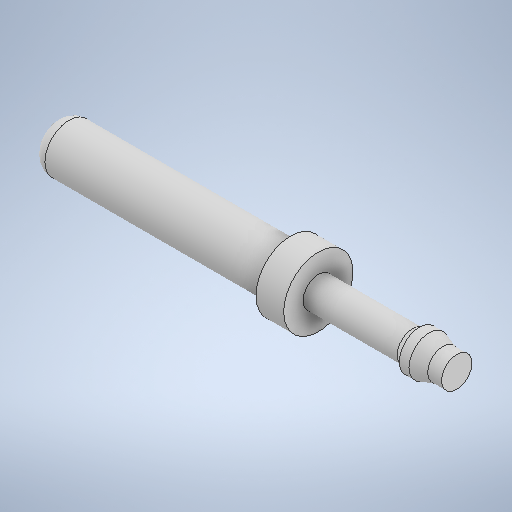
# Autodesk Inventor part: water_release_spring_v6
Saved by Autodesk Inventor 2025.2 (Build 292293000, 293)
## iProperties
Created: 2025-09-30
Part Number: water_release_spring_v6
Material: Generic
Document SubType Name: Modeling
Designer: Eden Salzig
Density: 1 g/cm^3
Appearance: Default
Author: Eden Salzig
Autodesk Inventor part; units mm, degrees
ref_plane "YZ Plane" through (0, 0, 0) normal (1, 0, 0) x (0, 1, 0)
ref_plane "XZ Plane" through (0, 0, 0) normal (0, 1, 0) x (-1, 0, 0)
ref_plane "XY Plane" through (0, 0, 0) normal (0, 0, 1) x (1, 0, 0)
sketch "Sketch1" plane through (0, 0, 0) normal (0, 1, 0) x (-1, 0, 0)
  line L0 (6.858, 3.683) -> (8.128, 2.794)
  line L1 (5.08, 3.683) -> (6.858, 3.683)
  line L2 (2.54, 2.794) -> (5.08, 3.683)
  line L3 (2.54, 2.794) -> (8.128, 2.794) construction
  line L4 (0, 2.794) -> (2.54, 2.794)
  line L5 (8.128, 2.794) -> (25.4, 2.794)
  line L6 (0, 0) -> (0, 2.794)
  line L7 (25.4, 2.794) -> (25.4, 0) construction
  line L8 (25.4, 0) -> (0, 0)
  line L9 (101.6, 0) -> (30.48, 0) construction
  line L10 (25.4, 0) -> (30.48, 0)
  line L11 (30.48, 0) -> (30.48, 4.445) construction
  line L12 (30.48, 6.35) -> (25.4, 6.35)
  line L13 (25.4, 6.35) -> (25.4, 2.794)
  line L14 (30.48, 0) -> (73.66, 0)
  line L15 (73.66, 0) -> (73.66, 4.445)
  line L16 (73.66, 4.445) -> (30.48, 4.445)
  line L17 (30.48, 4.445) -> (30.48, 0) construction
  line L18 (30.48, 4.445) -> (30.48, 6.35)
  line L19 (30.48, 0) -> (0, 0) construction
  line L20 (25.4, 2.794) -> (25.4, 0) construction
  dimension "d0" = 25.4
  dimension "d1" = 2.794
  dimension "d2" = 3.683
  dimension "d3" = 1.27
  dimension "d4" = 1.778
  dimension "d5" = 2.54
  dimension "d7" = 101.6
  dimension "d8" = 2.54
  dimension "d9" = 6.35
  dimension "d10" = 5.08
  dimension "d11" = 43.18
  dimension "d12" = 4.445
  constraints: 42 end point, 11 parallel, 6 horizontal, 4 perpendicular, 2 collinear, 1 coincident
  measures "d0" distance of L4.start L5.end
  measures "d1" distance of L8.end L4.start
  measures "d2" distance between parallel lines of L8 L1
  measures "d3" horizontal distance of L0.start L0.end
  measures "d4" distance of L2.end L0.start
  measures "d5" horizontal distance of L3.start L2.end
  measures "d7" distance of L9.start L8.end
  measures "d8" distance of L4.start L3.start
  measures "d9" distance of L12.end L7.end
  measures "d10" distance of L12.start L12.end
  measures "d11" distance of L15.end L11.end
  measures "d12" distance of L14.end L15.end
revolve "Revolution1" add sketch "Sketch1" angle 360 about axis through (-101.6, 0, 0) along (1, 0, 0)
fillet "Fillet1" radius 2.54 1 edges at (-73.66, 0, -4.445)
body "Solid1"
